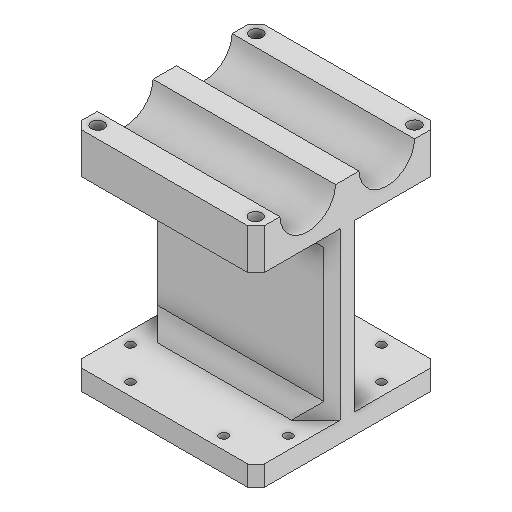
# Autodesk Inventor part: 3DP_PLA_Antenna_Boom_Coax_Feed_Horn_REVC
Saved by Autodesk Inventor 2027 (Build 310192060, 192F)
## iProperties
Created: 2026-01-18
Part Number: 3DP_PLA_Antenna_Boom_Coax_Feed_Horn_REVC
Material: Generic
Document SubType Name: Modeling
Designer: Andrzej
Density: 1 g/cm^3
Appearance: Default
Author: Andrzej
Autodesk Inventor part; units mm, degrees
ref_plane "YZ Plane" through (0, 0, 0) normal (1, 0, 0) x (0, 1, 0)
ref_plane "XZ Plane" through (0, 0, 0) normal (0, 1, 0) x (-1, 0, 0)
ref_plane "XY Plane" through (0, 0, 0) normal (0, 0, 1) x (1, 0, 0)
sketch "Sketch1" plane through (0, 0, 0) normal (0, 1, 0) x (-1, 0, 0)
  line L0 (45, 45) -> (-45, 45)
  line L1 (-45, 45) -> (-45, -45)
  line L2 (-45, -45) -> (45, -45)
  line L3 (45, -45) -> (45, 45)
  point P0 (0, 0)
  dimension "d0" = 90
  dimension "d1" = 90
  dimension "d2" = 45
  dimension "d3" = 45
  constraints: 8 end point, 2 parallel, 1 horizontal, 1 perpendicular
  measures "d0" distance of L0.start L0.end
  measures "d1" distance of L2.end L0.start
  measures "d2" distance from line of point (0, 0) L0
  measures "d3" distance from line of L3 point (0, 0)
extrude "Extrusion1" add sketch "Sketch1" along normal blind 20
sketch "Sketch2" plane through (45, 0, 45) normal (1, 0, 0) x (0, 0, -1)
  circle A0 centre (25.5, 20.5) radius 13.75
  circle A1 centre (64.5, 20.5) radius 13.75
  line L0 (0, 0) -> (90, 0) projected
  line L1 (90, 0) -> (90, 20) projected
  line L2 (0, 20) -> (90, 20) projected
  line L3 (0, 0) -> (0, 20) projected
  point P0 (45, 0)
  dimension "d6" = 27.5
  dimension "d7" = 27.5
  dimension "d8" = 0.5
  dimension "d9" = 39
  dimension "d10" = 90
  dimension "d11" = 25.5
  constraints: 2 centre point, 1 horizontal alignment
  measures "d6" diameter of A0
  measures "d7" diameter of A1
  measures "d8" distance from line of L2 A0.centre
  measures "d9" distance of A1.centre A0.centre
  measures "d10" distance between parallel lines of L1 L3
  measures "d11" distance from line of L3 A0.centre
extrude "Extrusion2" cut sketch "Sketch2" against normal through all contours A0 L2 | L2 A0 | L2 A1 | A1 L2
sketch "Sketch3" plane through (0, 0, 0) normal (0, -1, 0) x (1, 0, 0)
  line L0 (45, 45) -> (45, -45) projected
  line L1 (-45, 45) -> (45, 45) projected
  line L2 (-45, -45) -> (-45, 45) projected
  line L3 (45, -45) -> (-45, -45) projected
  line L4 (-45, -7.5) -> (45, -7.5)
  line L5 (-45, 7.5) -> (45, 7.5)
  line L6 (-7.5, -7.5) -> (-7.5, -45)
  line L7 (7.5, -7.5) -> (7.5, -45)
  line L8 (-7.5, 7.5) -> (-7.5, 45)
  line L9 (7.5, 7.5) -> (7.5, 45)
  line L10 (7.5, -7.5) -> (7.5, 7.5)
  line L11 (-7.5, -7.5) -> (-7.5, 7.5)
  point P0 (0, 0)
  dimension "d14" = 15
  dimension "d15" = 7.5
  dimension "d16" = 15
  dimension "d17" = 15
  dimension "d18" = 7.5
  dimension "d19" = 7.5
  constraints: 16 end point, 12 point on line, 6 perpendicular
  measures "d14" distance between parallel lines of L5 L4
  measures "d15" distance from line of point (0, 0) L4
  measures "d16" distance between parallel lines of L7 L6
  measures "d17" distance between parallel lines of L9 L8
  measures "d18" distance from line of point (0, 0) L6
  measures "d19" distance from line of point (0, 0) L8
extrude "Extrusion3" add sketch "Sketch3" along normal blind 91.75 contours L0 L4 L10 L5 | L10 L4 L11 L5 | L11 L4 L2 L5
sketch "Sketch4" plane through (0, 20, 0) normal (0, 1, 0) x (1, 0, 0)
  line L0 (-45, 33.2409) -> (45, 33.2409) projected
  line L1 (45, 33.2409) -> (45, 45) projected
  line L2 (45, 45) -> (-45, 45) projected
  line L3 (-45, 45) -> (-45, 33.2409) projected
  line L4 (45, -33.2409) -> (-45, -33.2409) projected
  line L5 (-45, -33.2409) -> (-45, -45) projected
  line L6 (-45, -45) -> (45, -45) projected
  line L7 (45, -45) -> (45, -33.2409) projected
  point P0 (0, 0)
  point P1 (39, 39.1205)
  point P2 (-39, 39.1205)
  point P3 (-39, -39.1205)
  point P4 (39, -39.1205)
  dimension "d22" = 6
  dimension "d23" = 6
  dimension "d24" = 11.7591
  dimension "d25" = 11.7591
  dimension "d26" = 5.8796
  dimension "d27" = 5.8796
  constraints: 2 horizontal alignment, 2 vertical alignment
  measures "d22" distance from line of point (39, 39.12) L1
  measures "d23" distance from line of L3 point (-39, 39.12)
  measures "d24" distance between parallel lines of L2 L0
  measures "d25" distance between parallel lines of L6 L4
  measures "d26" distance from line of L2 point (39, 39.12)
  measures "d27" distance from line of L6 point (39, -39.12)
hole "Hole1" at (39, 20, -39.1205) at (-39, 20, -39.1205) at (-39, 20, 39.1205) at (39, 20, 39.1205) direction (0, -1, 0) diameter 6.2 end through all
chamfer "Chamfer1" distance 4 angle 45 8 edges at (-45, 10, -45) (-45, 10, 45) (45, -45.875, -7.5) (45, -45.875, 7.5) (-45, -45.875, 7.5) (-45, -45.875, -7.5) (45, 10, 45) (45, 10, -45)
sketch "Sketch5" plane through (0, -91.75, 0) normal (0, -1, 0) x (1, 0, 0)
  line L0 (-45, -45) -> (45, -45)
  line L1 (45, -45) -> (45, 45)
  line L2 (45, 45) -> (-45, 45)
  line L3 (-45, 45) -> (-45, -45)
  point P0 (0, 0)
  point P1 (-38.9, -23)
  point P2 (-38.9, 23)
  point P3 (38.9, 23)
  point P4 (38.9, -23)
  point P5 (-23, 38.9)
  point P6 (23, 38.9)
  point P7 (-23, -38.9)
  point P8 (23, -38.9)
  dimension "d41" = 90
  dimension "d42" = 90
  dimension "d43" = 45
  dimension "d44" = 45
  dimension "d45" = 46
  dimension "d46" = 23
  dimension "d47" = 77.8
  dimension "d48" = 38.9
  dimension "d66" = 90
  constraints: 8 end point, 2 horizontal alignment, 2 parallel, 2 vertical alignment, 1 horizontal, 1 perpendicular, 5 other
  measures "d41" distance of L0.start L0.end
  measures "d42" distance of L0.end L1.end
  measures "d43" distance from line of point (0, 0) L0
  measures "d44" distance from line of point (0, 0) L3
  measures "d45" distance of point (-38.9, 23) point (-38.9, -23)
  measures "d46" vertical distance of point (0, 0) point (-38.9, -23)
  measures "d47" distance of point (38.9, -23) point (-38.9, -23)
  measures "d48" horizontal distance of point (-38.9, -23) point (0, 0)
extrude "Extrusion4" add sketch "Sketch5" against normal blind 10
hole "Hole2" at (-38.9, -91.75, -23) at (-38.9, -91.75, 23) at (38.9, -91.75, 23) at (38.9, -91.75, -23) at (23, -91.75, -38.9) at (-23, -91.75, -38.9) at (-23, -91.75, 38.9) at (23, -91.75, 38.9) direction (0, 1, 0) diameter 4.2 depth 10
chamfer "Chamfer4" distance 8 angle 45 4 edges at (0, 0, 7.5) (0, 0, -7.5) (0, -81.75, -7.5) (0, -81.75, 7.5)
chamfer "Chamfer5" distance 4 angle 45 4 edges at (45, -86.75, 45) (45, -86.75, -45) (-45, -86.75, -45) (-45, -86.75, 45)
equation "\"d1\" = d0"
equation "\"d2\" = 0.5 * d1"
equation "\"d3\" = 0.5 * d0"
equation "\"d11\" = -0.5 * d9 + 0.5 * d10"
equation "\"d15\" = 0.5 * d14"
equation "\"d16\" = d14"
equation "\"d17\" = d16"
equation "\"d18\" = 0.5 * d14"
equation "\"d19\" = d18"
equation "\"d23\" = d22"
equation "\"d26\" = 0.5 * d24"
equation "\"d27\" = 0.5 * d25"
equation "\"d42\" = d41"
equation "\"d43\" = 0.5 * d42"
equation "\"d44\" = 0.5 * d41"
equation "\"d46\" = 0.5 * d45"
equation "\"d48\" = 0.5 * d47"
body "Solid1"
